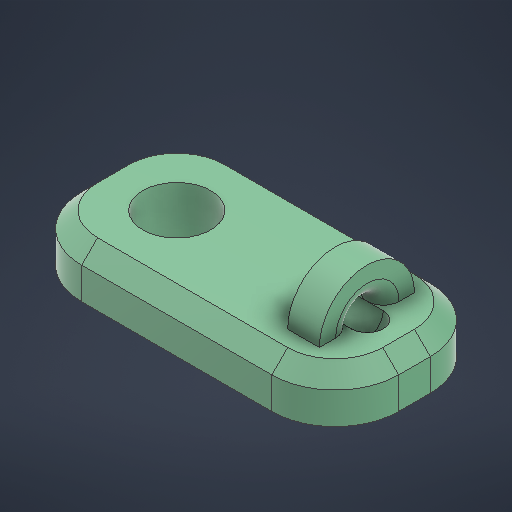
# Autodesk Inventor part: 1_1_6_attache_cable
Saved by Autodesk Inventor 2026 (Build 300175000, 175)
## iProperties
Created: 2025-05-07
Part Number: 1_1_6_attache_cable
Material: Generic
Document SubType Name: Modeling
Designer: remg9
Density: 1 g/cm^3
Appearance: Default
Author: remg9
Autodesk Inventor part; units mm, degrees
ref_plane "YZ Plane" through (0, 0, 0) normal (1, 0, 0) x (0, 1, 0)
ref_plane "XZ Plane" through (0, 0, 0) normal (0, 1, 0) x (-1, 0, 0)
ref_plane "XY Plane" through (0, 0, 0) normal (0, 0, 1) x (1, 0, 0)
sketch "Sketch1" plane through (0, 0, 0) normal (0, 1, 0) x (-1, 0, 0)
  line L0 (4, 0) -> (16, 0)
  line L1 (20, -4) -> (20, -6)
  line L2 (16, -10) -> (4, -10)
  line L3 (0, -6) -> (0, -4)
  arc A0 (16, -10) -> (20, -6) centre (16, -6) ccw
  arc A1 (20, -4) -> (16, 0) centre (16, -4) ccw
  arc A2 (0, -6) -> (4, -10) centre (4, -6) ccw
  arc A3 (4, 0) -> (0, -4) centre (4, -4) ccw
  circle A4 centre (15, -5) radius 2.15
  point P0 (0, 0)
  point P1 (20, -10)
  point P2 (0, -10)
  dimension "d0" = 10
  dimension "d1" = 20
  dimension "d2" = 4
  dimension "d3" = 5
  dimension "d4" = 5
  dimension "d5" = 4.3
  constraints: 8 end point, 8 point on circle, 8 tangent, 6 point on line, 5 centre point, 3 equal radius, 2 parallel, 1 horizontal, 1 perpendicular
  measures "d0" distance of point (0, -10) point (0, 0)
  measures "d1" distance of point (20, -10) point (0, -10)
  measures "d2" radius of A0
  measures "d3" distance from line of L0 A4.centre
  measures "d4" horizontal distance of L1.end A4.centre
  measures "d5" diameter of A4
extrude "Extrusion1" add sketch "Sketch1" along normal blind 3
chamfer "Chamfer1" distance 1 angle 45 8 edges at (-1.1716, 3, -1.1716) (0, 3, -5) (-1.1716, 3, -8.8284) (-10, 3, -10) (-18.8284, 3, -8.8284) (-20, 3, -5) (-18.8284, 3, -1.1716) (-10, 3, 0)
sketch "Sketch2" plane through (0, 3, 0) normal (0, 1, 0) x (1, 0, 0)
  line L0 (-5, 2) -> (-3, 2)
  line L1 (-3, 2) -> (-3, 8)
  line L2 (-3, 8) -> (-5, 8)
  line L3 (-5, 8) -> (-5, 2)
  line L4 (0, 4) -> (0, 6) projected
  line L5 (-4, 10) -> (-16, 10) projected
  line L6 (-16, 0) -> (-4, 0) projected
  point P0 (0, 0)
  point P1 (-3, 5)
  dimension "d11" = 3
  dimension "d12" = 2
  dimension "d13" = 2
  dimension "d14" = 2
  constraints: 8 end point, 2 parallel, 1 horizontal, 1 midpoint, 1 perpendicular
  measures "d11" distance from line of L4 point (-3, 5)
  measures "d12" distance between parallel lines of L5 L2
  measures "d13" distance between parallel lines of L6 L0
  measures "d14" distance of L1.end L2.end
extrude "Extrusion2" add sketch "Sketch2" along normal blind 3
fillet "Fillet1" radius 3 2 edges at (-4, 6, -2) (-4, 6, -8)
sketch "Sketch3" plane through (-3, 3, -2) normal (1, 0, 0) x (0, 0, -1)
  circle A0 centre (3.0295, 0) radius 1
  line L0 (4, 0) -> (2, 0) projected
  point P0 (-2, -3)
  dimension "d18" = 0
  dimension "d19" = 2
  constraints: 1 centre point
  measures "d18" distance from line of L0 A0.centre
  measures "d19" diameter of A0
extrude "Extrusion3" cut sketch "Sketch3" along normal blind 1 and the other way blind 3
fillet "Fillet2" radius 1 4 edges at (-6, 2, -5.0295) (-2, 2, -5.0295) (-3, 4, -5.0295) (-5, 4, -5.0295)
body "Solid1"
